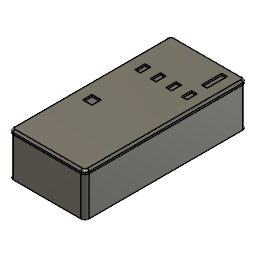
C_involucro_modulo_controle (Autodesk Fusion 360 design; units mm, degrees)
Autodesk Fusion 360 part; units mm, degrees
(part 1 of 2)
sketch "Esboço1" plane through (0, 0, 0) normal (0, 0, 1) x (1, 0, 0)
  line L0 (0, 0) -> (28, 0)
  line L1 (0, 0) -> (0, 10)
  line L2 (0, 10) -> (4, 10)
  line L3 (4, 10) -> (4, 8)
  line L4 (4, 8) -> (2, 8)
  line L5 (2, 8) -> (2, 6)
  line L6 (2, 6) -> (4, 6)
  line L7 (4, 6) -> (4, 4)
  line L8 (4, 4) -> (2, 4)
  line L9 (2, 4) -> (2, 2)
  line L10 (2, 2) -> (28, 2)
  line L11 (28, 2) -> (28, 0)
  line L12 (28, 2) -> (28, 0)
  line L13 (28, 2) -> (28, 0)
  line L14 (56, 0) -> (28, 0)
  line L15 (52, 4) -> (54, 4)
  line L16 (54, 2) -> (28, 2)
  line L17 (56, 10) -> (52, 10)
  line L18 (52, 10) -> (52, 8)
  line L19 (54, 4) -> (54, 2)
  line L20 (54, 6) -> (52, 6)
  line L21 (28, 2) -> (28, 0)
  line L22 (52, 6) -> (52, 4)
  line L23 (52, 8) -> (54, 8)
  line L24 (54, 8) -> (54, 6)
  line L25 (56, 0) -> (56, 10)
  point P0 (56, 0)
  dimension "d2" = 10
  dimension "d3" = 4
  dimension "d4" = 2
  dimension "d5" = 2
  dimension "d6" = 2
  dimension "d7" = 2
  dimension "d8" = 2
  dimension "d9" = 2
  dimension "d10" = 2
  dimension "d11" = 26
  constraint coincident L0.start L1.start
  constraint horizontal L0
  constraint perpendicular L0 L1
  constraint perpendicular L1 L2
  constraint perpendicular L2 L3
  constraint perpendicular L1 L4
  constraint perpendicular L4 L5
  constraint perpendicular L5 L6
  constraint perpendicular L6 L7
  constraint perpendicular L7 L8
  constraint perpendicular L0 L9
  constraint perpendicular L9 L10
  constraint symmetric L10.end L11 L12.start
  constraint symmetric L0.end L11 L12.end
  constraint perpendicular L10 L12
  constraint symmetric L0.start L12 L14.start
  constraint symmetric L0.start L12 P0
  constraint symmetric L1.end L12 L17.start
  constraint symmetric L2.end L12 L17.end
  constraint symmetric L3.end L12 L18.end
  constraint symmetric L4.end L12 L23.end
  constraint symmetric L5.end L12 L20.start
  constraint symmetric L6.end L12 L20.end
  constraint symmetric L7.end L12 L15.start
  constraint symmetric L8.end L12 L15.end
  constraint symmetric L9.end L12 L16.start
  constraint symmetric L10.end L12 L11.start
  constraint symmetric L0.end L12 L11.end
  measures "d2" distance of L0.start L1.end
  measures "d3" distance of L1.end L2.end
  measures "d4" distance of L2.end L3.end
  measures "d5" distance of L3.end L4.end
  measures "d6" distance of L4.end L5.end
  measures "d7" distance of L5.end L6.end
  measures "d8" distance of L6.end L7.end
  measures "d9" distance of L7.end L8.end
  measures "d10" distance of L8.end L9.end
  measures "d11" distance of L9.end L10.end
extrude "Extrusão1" add sketch "Esboço1" along normal blind 75 makes body 1
fillet "Arredondamento1" radius 2 1 edges at (0, 10, 37.5) on bodies 1
fillet "Arredondamento1" radius 2 1 edges at (56, 10, 37.5) on bodies 1
sketch "Esboço3" plane through (0, 0, 75) normal (0, 0, 1) x (1, 0, 0)
  line L0 (54, 2) -> (2, 2)
  line L1 (2, 2) -> (2, 4)
  line L2 (2, 4) -> (4, 4)
  line L3 (4, 4) -> (4, 6)
  line L4 (4, 6) -> (2, 6)
  line L5 (2, 6) -> (2, 8)
  line L6 (2, 8) -> (4, 8)
  line L7 (4, 8) -> (4, 10)
  line L8 (4, 10) -> (2, 10)
  arc A0 (2, 10) -> (0, 8) centre (2, 8) ccw
  line L9 (0, 8) -> (0, 0)
  line L10 (0, 0) -> (56, 0)
  line L11 (2, 8) -> (4, 8)
  line L12 (4, 8) -> (4, 6)
  line L13 (4, 6) -> (2, 6)
  line L14 (2, 6) -> (2, 8)
  line L15 (52, 8) -> (54, 8)
  line L16 (54, 8) -> (54, 6)
  line L17 (54, 6) -> (52, 6)
  line L18 (52, 6) -> (52, 8)
  line L19 (56, 0) -> (56, 8)
  line L20 (54, 10) -> (52, 10)
  line L21 (52, 10) -> (52, 8)
  line L22 (52, 8) -> (54, 8)
  line L23 (54, 8) -> (54, 6)
  line L24 (54, 6) -> (52, 6)
  line L25 (52, 6) -> (52, 4)
  line L26 (52, 4) -> (54, 4)
  line L27 (54, 4) -> (54, 2)
  arc A1 (56, 8) -> (54, 10) centre (54, 8) ccw
  constraint horizontal L11
  constraint vertical L12
  constraint horizontal L13
  constraint vertical L14
  constraint coincident L3.end L4.start
  constraint coincident L5.end L6.start
  constraint horizontal L15
  constraint vertical L16
  constraint horizontal L17
  constraint vertical L18
copy_body "Corpo -> Componente1" bodies 1 removing the originals makes body 2 in component "Placa 5x7"
extrude "Extrusão1'" add sketch "Esboço3" against normal blind 2 contours L15 L16 L17 L18 L22 L23 L24 | L4 L5 L6 L11 L12 L13 L14 bodies 2 in component "Placa 5x7"
sketch "Esboço7" plane through (0, 0, 0) normal (0, -1, 0) x (1, 0, 0)
  line L0 (0, 0) -> (56, 0)
  line L1 (56, 75) -> (0, 75)
  line L2 (0, 75) -> (0, 0)
  line L3 (0, 0) -> (0, 37.5)
  line L4 (0, 37.5) -> (28, 37.5)
  line L5 (67, -48.75) -> (-11, -48.75)
  line L6 (-11, -48.75) -> (-11, 123.75)
  line L7 (-11, 123.75) -> (67, 123.75)
  line L8 (67, 123.75) -> (67, -48.75)
  line L9 (67, -48.75) -> (-11, 123.75) construction
  line L10 (-11, -48.75) -> (67, 123.75) construction
  line L11 (65, 125.75) -> (-9, 125.75)
  line L12 (-13, 121.75) -> (-13, -46.75)
  line L13 (-9, -50.75) -> (65, -50.75)
  line L14 (69, -46.75) -> (69, 121.75)
  line L15 (69, 125.75) -> (-13, -50.75) construction
  line L16 (-13, 125.75) -> (69, -50.75) construction
  arc A0 (-9, 125.75) -> (-13, 121.75) centre (-9, 121.75) ccw
  arc A1 (69, 121.75) -> (65, 125.75) centre (65, 121.75) ccw
  arc A2 (65, -50.75) -> (69, -46.75) centre (65, -46.75) ccw
  arc A3 (-13, -46.75) -> (-9, -50.75) centre (-9, -46.75) ccw
  line L17 (56, 0) -> (56, 75)
  point P0 (28, 37.5)
  point P1 (28, 37.5)
  dimension "d45" = 37.5
  dimension "d46" = 28
  dimension "d47" = 172.5
  dimension "d48" = 78
  dimension "d49" = 82
  dimension "d50" = 176.5
  dimension "d54" = 4
  constraint coincident L0.start L2.end
  constraint perpendicular L0 L3
  constraint perpendicular L3 L4
  constraint horizontal L5
  constraint perpendicular L5 L6
  constraint parallel L5 L7
  constraint parallel L6 L8
  constraint coincident L9 P1
  constraint coincident L10 P1
  constraint coincident P1 P0
  constraint horizontal L11
  constraint perpendicular L11 L12
  constraint parallel L11 L13
  constraint parallel L12 L14
  constraint coincident L15 P1
  constraint coincident L16 P1
  constraint coincident L16.start L12
  constraint coincident L16.start L11
  constraint tangent L12 A0
  constraint tangent L11 A0
  constraint coincident L15.start L11
  constraint coincident L15.start L14
  constraint tangent L11 A1
  constraint tangent L14 A1
  constraint equal A0 A1
  constraint coincident L16.end L13
  constraint coincident L16.end L14
  constraint tangent L13 A2
  constraint tangent L14 A2
  constraint equal A0 A2
  constraint coincident L15.end L13
  constraint coincident L15.end L12
  constraint tangent L13 A3
  constraint tangent L12 A3
  constraint equal A0 A3
  measures "d45" distance of L0.start L3.end
  measures "d46" distance of L3.end P1
  measures "d47" distance of L5.end L6.end
  measures "d48" distance of L6.end L7.end
  measures "d49" distance of L15.end L16.end
  measures "d50" distance of L16.start L15.end
  measures "d54" radius of A0
extrude "Extrusão8" add sketch "Esboço7" against normal blind 41 thin wall 1 centred separate body contours L11 L12 L13 L14 A0 A1 A2 A3 makes body 3
copy_body "Corpo -> Componente2" bodies 3 removing the originals makes body 4 in component "Suporte Placa (1)"
extrude "Extrusão1''" add sketch "Esboço7" along normal blind 2 contours L0 L1 L2 L3 L17 | L5 L6 L7 L8 | L11 L12 L13 L14 A0 A1 A2 A3 bodies 4 in component "Suporte Placa (1)"
extrude "Extrusão11" add 1 faces at (41.6667, -2, 65.5833) along direction (0, 1, 0) blind 2 thin wall 0.5 outside on bodies 4 bodies 4 in component "Suporte Placa (1)"
sketch "Esboço1 (2)" plane through (0, 41, 0) normal (0, 1, 0) x (-1, 0, 0) in component "Suporte Placa (1)"
  arc A0 (12.5, 121.75) -> (11.5, 124.1995) centre (9, 121.75) ccw
  line L0 (12.5, 121.75) -> (12.5, -46.75)
  arc A1 (11.5, -49.1995) -> (12.5, -46.75) centre (9, -46.75) ccw
  line L1 (11.5, -49.1995) -> (11.5, 124.1995)
  arc A2 (-65, 125.25) -> (-67.4495, 124.25) centre (-65, 121.75) ccw
  line L2 (-65, 125.25) -> (9, 125.25)
  arc A3 (11.4495, 124.25) -> (9, 125.25) centre (9, 121.75) ccw
  line L3 (11.4495, 124.25) -> (-67.4495, 124.25)
  arc A4 (9, -50.25) -> (11.4495, -49.25) centre (9, -46.75) ccw
  line L4 (9, -50.25) -> (-65, -50.25)
  arc A5 (-67.4495, -49.25) -> (-65, -50.25) centre (-65, -46.75) ccw
  line L5 (-67.4495, -49.25) -> (11.4495, -49.25)
  arc A6 (-68.5, -46.75) -> (-67.5, -49.1995) centre (-65, -46.75) ccw
  line L6 (-68.5, -46.75) -> (-68.5, 121.75)
  arc A7 (-67.5, 124.1995) -> (-68.5, 121.75) centre (-65, 121.75) ccw
  line L7 (-67.5, 124.1995) -> (-67.5, -49.1995)
  line L8 (-66.5, 123.25) -> (10.5, 123.25)
  line L9 (10.5, 123.25) -> (10.5, -48.25)
  line L10 (10.5, -48.25) -> (-66.5, -48.25)
  line L11 (-66.5, -48.25) -> (-66.5, 123.25)
  arc A8 (9, -51.25) -> (13.5, -46.75) centre (9, -46.75) ccw
  line L12 (13.5, -46.75) -> (13.5, 121.75)
  arc A9 (13.5, 121.75) -> (9, 126.25) centre (9, 121.75) ccw
  line L13 (9, 126.25) -> (-65, 126.25)
  arc A10 (-65, 126.25) -> (-69.5, 121.75) centre (-65, 121.75) ccw
  line L14 (-69.5, 121.75) -> (-69.5, -46.75)
  line L15 (-65, -51.25) -> (9, -51.25)
  line L16 (10.5, -48.25) -> (10.5, -46.25)
  line L17 (10.5, -48.25) -> (8.5, -48.25)
  line L18 (8.5, -48.25) -> (8.5, -51.25)
  line L19 (10.5, -46.25) -> (13.5, -46.25)
  line L20 (-42.25, -3.25) -> (-42.75, -3.25)
  line L21 (-47.25, 1.25) -> (-47.25, 1.75)
  line L22 (-28, -51.25) -> (-28, -15.5)
  line L23 (-28, -15.5) -> (13.5, 37.5)
  arc A11 (-68.2911, 17.2939) -> (-71.5805, 11.846) centre (-67.2118, 12.9253) ccw
  line L24 (-68.5481, 12.0801) -> (-71.4606, 11.3606)
  line L25 (-69.0278, 14.0218) -> (-68.5481, 12.0801)
  line L26 (-67.0862, 14.5014) -> (-67.8057, 17.4139)
  line L27 (-67.0862, 14.5014) -> (10.5, 123.25)
  line L28 (-66.5, -46.25) -> (-69.5, -46.25)
  line L29 (-66.5, -48.25) -> (-66.5, -46.25)
  line L30 (-66.5, -48.25) -> (-64.5, -48.25)
  line L31 (-64.5, -48.25) -> (-64.5, -51.25)
  arc A12 (-69.5, -46.75) -> (-65, -51.25) centre (-65, -46.75) ccw
  line L32 (11.0862, 14.5014) -> (11.8057, 17.4139)
  line L33 (11.0862, 14.5014) -> (-66.5, 123.25)
  line L34 (13.0278, 14.0218) -> (12.5481, 12.0801)
  line L35 (12.5481, 12.0801) -> (15.4606, 11.3606)
  arc A13 (15.5805, 11.846) -> (12.2911, 17.2939) centre (11.2118, 12.9253) ccw
  dimension "d57" = 2
  dimension "d58" = 2
  dimension "d59" = 35.75
  constraint coincident L9.end L10.start
  constraint perpendicular L10 L16
  constraint perpendicular L16 L17
  constraint coincident L15 L18.end
  constraint perpendicular L15 L18
  constraint coincident L12 L19.end
  constraint perpendicular L12 L19
  constraint midpoint L15 L22.start
  constraint perpendicular L10 L22
  constraint midpoint L12 L23.end
  constraint symmetric A8.start L23 A11.end
  constraint symmetric A8.end L23 A11.start
  constraint symmetric A8 L23 A11
  constraint symmetric L16.end L23 L26.start
  constraint symmetric L9.end L23 L25.start
  constraint symmetric L17.end L23 L24.start
  constraint symmetric L18.end L23 L24.end
  constraint symmetric L19.end L23 L26.end
  constraint coincident L8.end L9.start
  constraint symmetric A8.start L22 L15.start
  constraint symmetric A8.end L22 L14.end
  constraint symmetric A8 L22 A12
  constraint symmetric L9.end L22 L10.end
  constraint symmetric L16.end L22 L28.start
  constraint symmetric L17.end L22 L30.end
  constraint symmetric L18.end L22 L31.end
  constraint symmetric L19.end L22 L28.end
  constraint symmetric L22 A11.end A13.start
  constraint symmetric L22 A11.start A13.end
  constraint symmetric L22 A11 A13
  constraint symmetric L22 L24.start L34.end
  constraint symmetric L22 L24.end L35.end
  constraint symmetric L22 L25.start L34.start
  constraint symmetric L22 L26.start L32.start
  constraint symmetric L22 L26.end L32.end
  constraint symmetric L22 L8.end L8.start
  measures "d57" distance of L9.end L16.end
  measures "d58" distance of L9.end L17.end
  measures "d59" distance of L22.start L22.end
ref_plane "Plano de trabalho1" through (28, 41, 37.5) normal (0, 1, 0) x (-1, 0, 0) in component "Suporte Placa (1)"
sketch "Esboço3 (2)" plane through (0, 41, 0) normal (0, 1, 0) x (1, 0, 0) in component "Suporte Placa (1)"
extrude "Extrusão7" add 1 faces at (67.1667, 41, 8.9167) along direction (0, 1, 0) blind 2 separate body on bodies 4 makes body 5 in component "Suporte Placa (1)"
copy_body "CutPasteBodies1" bodies 5 removing the originals makes body 6 in component "Tampa"
sketch "Esboço1 (3)" plane through (0, 43, 0) normal (0, 1, 0) x (-1, 0, 0) in component "Tampa"
  line L0 (-66.5, -48.25) -> (-66.5, 123.25)
  line L1 (-66.5, 123.25) -> (10.5, 123.25)
  line L2 (10.5, 123.25) -> (10.5, -48.25)
  line L3 (10.5, -48.25) -> (-66.5, -48.25)
  line L4 (-67.5, 124.1995) -> (-67.5, -49.1995)
  line L5 (-68.5, -46.75) -> (-68.5, 121.75)
  line L6 (-69.5, 121.75) -> (-69.5, -46.75)
  arc A0 (-69.5, -46.75) -> (-65, -51.25) centre (-65, -46.75) ccw
  line L7 (-65, -51.25) -> (9, -51.25)
  arc A1 (9, -51.25) -> (13.5, -46.75) centre (9, -46.75) ccw
  line L8 (13.5, -46.75) -> (13.5, 121.75)
  arc A2 (13.5, 121.75) -> (9, 126.25) centre (9, 121.75) ccw
  line L9 (9, 126.25) -> (-65, 126.25)
  arc A3 (-65, 126.25) -> (-69.5, 121.75) centre (-65, 121.75) ccw
  line L10 (12.5, 121.75) -> (12.5, -46.75)
  line L11 (11.5, -49.1995) -> (11.5, 124.1995)
  line L12 (-65, 125.25) -> (9, 125.25)
  line L13 (11.4495, 124.25) -> (-67.4495, 124.25)
  line L14 (9, -50.25) -> (-65, -50.25)
  line L15 (-67.4495, -49.25) -> (11.4495, -49.25)
  arc A4 (12.5, 121.75) -> (11.5, 124.1995) centre (9, 121.75) ccw
  arc A5 (11.5, -49.1995) -> (12.5, -46.75) centre (9, -46.75) ccw
  arc A6 (-65, 125.25) -> (-67.4495, 124.25) centre (-65, 121.75) ccw
  arc A7 (11.4495, 124.25) -> (9, 125.25) centre (9, 121.75) ccw
  arc A8 (9, -50.25) -> (11.4495, -49.25) centre (9, -46.75) ccw
  arc A9 (-67.4495, -49.25) -> (-65, -50.25) centre (-65, -46.75) ccw
  arc A10 (-68.5, -46.75) -> (-67.5, -49.1995) centre (-65, -46.75) ccw
  arc A11 (-67.5, 124.1995) -> (-68.5, 121.75) centre (-65, 121.75) ccw
extrude "Extrusão1'''" add sketch "Esboço1 (3)" along normal blind 2 contours L0 L1 L2 L3 | L4 L5 A10 A11 | L6 A0 L7 A1 L8 A2 L9 A3 | L10 L11 A4 A5 | L12 L13 A6 A7 | L14 L15 A8 A9 bodies 6 in component "Tampa"
extrude "Extrusão6" add sketch "Esboço1 (3)" along normal blind 2 and the other way blind 4 contours L4 L5 A10 A11 | L10 L11 A4 A5 | L12 L13 A6 A7 | L14 L15 A8 A9 bodies 6 in component "Tampa"
fillet "Arredondamento1'" radius 2 8 edges at (69.5, 45, 37.5) (68.182, 45, -49.932) (28, 45, -51.25) (-12.182, 45, -49.932) (-13.5, 45, 37.5) (-12.182, 45, 124.932) (28, 45, 126.25) (68.182, 45, 124.932) on bodies 6 in component "Tampa"
sketch "Esboço11" plane through (0, 45, 0) normal (0, 1, 0) x (-1, 0, 0)
  line L0 (-67.5, 121.75) -> (-67.5, -46.75)
  arc A0 (-67.5, -46.75) -> (-65, -49.25) centre (-65, -46.75) ccw
  line L1 (-65, -49.25) -> (9, -49.25)
  arc A1 (9, -49.25) -> (11.5, -46.75) centre (9, -46.75) ccw
  line L2 (11.5, -46.75) -> (11.5, 121.75)
  arc A2 (11.5, 121.75) -> (9, 124.25) centre (9, 121.75) ccw
  line L3 (9, 124.25) -> (-65, 124.25)
  arc A3 (-65, 124.25) -> (-67.5, 121.75) centre (-65, 121.75) ccw
  spline S0 degree 3 poles (-31.7483, 30.1834) (-31.8055, 30.363) (-32.0097, 30.8122) (-32.1975, 31.1797) knots 0 0 0 0 1 1 1 1
  line L4 (-32.1975, 31.1797) -> (-32.5487, 31.8576)
  line L5 (-32.5487, 31.8576) -> (-33.3408, 32.0944)
  spline S1 degree 3 poles (-33.3408, 32.0944) (-35.6847, 32.8131) (-37.2037, 33.2541) (-37.2364, 33.2296) knots 0 0 0 0 1 1 1 1
  spline S2 degree 3 poles (-37.2364, 33.2296) (-37.2528, 33.2133) (-37.1221, 32.9192) (-36.9424, 32.5762) knots 0 0 0 0 1 1 1 1
  spline S3 degree 3 poles (-36.9424, 32.5762) (-36.1992, 31.1552) (-36.2319, 30.1752) (-37.0567, 29.2605) knots 0 0 0 0 1 1 1 1
  line L6 (-37.0567, 29.2605) -> (-37.3589, 28.9257)
  line L7 (-37.3589, 28.9257) -> (-37.0894, 28.8522)
  spline S4 degree 3 poles (-37.0894, 28.8522) (-36.9424, 28.8113) (-35.8726, 28.4928) (-34.7129, 28.1417) knots 0 0 0 0 1 1 1 1
  line L8 (-34.7129, 28.1417) -> (-32.6058, 27.5128)
  line L9 (-32.6058, 27.5128) -> (-32.3608, 27.7415)
  spline S5 degree 3 poles (-32.3608, 27.7415) (-32.2302, 27.8722) (-32.0097, 28.1907) (-31.879, 28.4602) knots 0 0 0 0 1 1 1 1
  spline S6 degree 3 poles (-31.879, 28.4602) (-31.6095, 28.9992) (-31.5605, 29.5954) (-31.7483, 30.1834) knots 0 0 0 0 1 1 1 1
  spline S7 degree 3 poles (-32.663, 27.2433) (-32.6793, 27.1943) (-32.908, 26.3613) (-33.1775, 25.3813) knots 0 0 0 0 1 1 1 1
  spline S8 degree 3 poles (-33.1775, 25.3813) (-33.4389, 24.4013) (-33.6757, 23.5764) (-33.7002, 23.5519) knots 0 0 0 0 1 1 1 1
  spline S9 degree 3 poles (-33.7002, 23.5519) (-33.7247, 23.5274) (-34.5495, 23.7479) (-35.5296, 24.0338) knots 0 0 0 0 1 1 1 1
  line L10 (-35.5296, 24.0338) -> (-37.3099, 24.5564)
  line L11 (-37.3099, 24.5564) -> (-37.3344, 26.7125)
  line L12 (-37.3344, 26.7125) -> (-37.3589, 28.8767)
  line L13 (-37.3589, 28.8767) -> (-37.8816, 26.9575)
  spline S10 degree 3 poles (-37.8816, 26.9575) (-38.3798, 25.1444) (-38.4043, 24.9893) (-38.4124, 24.1318) knots 0 0 0 0 1 1 1 1
  line L14 (-38.4124, 24.1318) -> (-38.4124, 23.2252)
  line L15 (-38.4124, 23.2252) -> (-37.5304, 22.9802)
  line L16 (-37.5304, 22.9802) -> (-36.6566, 22.7352)
  line L17 (-36.6566, 22.7352) -> (-36.6321, 22.1636)
  line L18 (-36.6321, 22.1636) -> (-36.6076, 21.5919)
  line L19 (-36.6076, 21.5919) -> (-36.1257, 21.4612)
  spline S11 degree 3 poles (-36.1257, 21.4612) (-35.8562, 21.3795) (-35.6031, 21.3224) (-35.5541, 21.3224) knots 0 0 0 0 1 1 1 1
  spline S12 degree 3 poles (-35.5541, 21.3224) (-35.5051, 21.3224) (-35.4724, 21.5511) (-35.4724, 21.8614) knots 0 0 0 0 1 1 1 1
  spline S13 degree 3 poles (-35.4724, 21.8614) (-35.4724, 22.3187) (-35.4561, 22.3922) (-35.3417, 22.3514) knots 0 0 0 0 1 1 1 1
  spline S14 degree 3 poles (-35.3417, 22.3514) (-35.2682, 22.3269) (-35.1212, 22.2779) (-35.015, 22.2534) knots 0 0 0 0 1 1 1 1
  spline S15 degree 3 poles (-35.015, 22.2534) (-34.8272, 22.2044) (-34.819, 22.1717) (-34.819, 21.5592) knots 0 0 0 0 1 1 1 1
  line L20 (-34.819, 21.5592) -> (-34.819, 20.9222)
  line L21 (-34.819, 20.9222) -> (-34.3454, 20.7834)
  spline S16 degree 3 poles (-34.3454, 20.7834) (-34.0922, 20.7099) (-33.8309, 20.6282) (-33.7737, 20.6119) knots 0 0 0 0 1 1 1 1
  spline S17 degree 3 poles (-33.7737, 20.6119) (-33.7002, 20.5792) (-33.6757, 20.8895) (-33.6757, 22.0084) knots 0 0 0 0 1 1 1 1
  line L22 (-33.6757, 22.0084) -> (-33.6757, 23.4458)
  line L23 (-33.6757, 23.4458) -> (-33.447, 23.3967)
  spline S18 degree 3 poles (-33.447, 23.3967) (-33.3245, 23.3641) (-33.1448, 23.3069) (-33.0387, 23.2742) knots 0 0 0 0 1 1 1 1
  spline S19 degree 3 poles (-33.0387, 23.2742) (-32.5977, 23.1109) (-32.614, 23.0374) (-32.6222, 25.2588) knots 0 0 0 0 1 1 1 1
  spline S20 degree 3 poles (-32.6222, 25.2588) (-32.6222, 26.394) (-32.6385, 27.2842) (-32.663, 27.2433) knots 0 0 0 0 1 1 1 1
  spline S21 degree 3 poles (-33.6757, 7.9778) (-33.8227, 8.4597) (-34.2719, 9.0232) (-34.6557, 9.211) knots 0 0 0 0 1 1 1 1
  spline S22 degree 3 poles (-34.6557, 9.211) (-35.3009, 9.5377) (-35.6684, 9.4315) (-36.5096, 8.6557) knots 0 0 0 0 1 1 1 1
  spline S23 degree 3 poles (-36.5096, 8.6557) (-36.7056, 8.476) (-36.8852, 8.3372) (-36.9261, 8.3372) knots 0 0 0 0 1 1 1 1
  spline S24 degree 3 poles (-36.9261, 8.3372) (-36.9669, 8.3372) (-37.0649, 8.4107) (-37.1466, 8.5005) knots 0 0 0 0 1 1 1 1
  spline S25 degree 3 poles (-37.1466, 8.5005) (-37.3589, 8.7373) (-37.3263, 9.162) (-37.0812, 9.5867) knots 0 0 0 0 1 1 1 1
  line L24 (-37.0812, 9.5867) -> (-36.8689, 9.9379)
  line L25 (-36.8689, 9.9379) -> (-37.4733, 10.1175)
  spline S26 degree 3 poles (-37.4733, 10.1175) (-37.8081, 10.2155) (-38.1184, 10.2972) (-38.1593, 10.2972) knots 0 0 0 0 1 1 1 1
  spline S27 degree 3 poles (-38.1593, 10.2972) (-38.2001, 10.2972) (-38.2981, 10.1339) (-38.3716, 9.9297) knots 0 0 0 0 1 1 1 1
  spline S28 degree 3 poles (-38.3716, 9.9297) (-38.5758, 9.407) (-38.5104, 8.2718) (-38.2573, 7.7655) knots 0 0 0 0 1 1 1 1
  spline S29 degree 3 poles (-38.2573, 7.7655) (-38.0204, 7.3) (-37.7183, 6.9733) (-37.3508, 6.7936) knots 0 0 0 0 1 1 1 1
  spline S30 degree 3 poles (-37.3508, 6.7936) (-36.6157, 6.418) (-36.2564, 6.5078) (-35.6031, 7.1938) knots 0 0 0 0 1 1 1 1
  spline S31 degree 3 poles (-35.6031, 7.1938) (-35.3499, 7.4633) (-35.0967, 7.6838) (-35.0395, 7.6838) knots 0 0 0 0 1 1 1 1
  spline S32 degree 3 poles (-35.0395, 7.6838) (-34.7129, 7.6838) (-34.623, 7.006) (-34.9007, 6.5568) knots 0 0 0 0 1 1 1 1
  spline S33 degree 3 poles (-34.9007, 6.5568) (-35.0885, 6.2546) (-35.1212, 6.2873) (-34.3372, 6.0505) knots 0 0 0 0 1 1 1 1
  line L26 (-34.3372, 6.0505) -> (-33.8309, 5.9034)
  line L27 (-33.8309, 5.9034) -> (-33.741, 6.1158)
  spline S34 degree 3 poles (-33.741, 6.1158) (-33.6185, 6.4098) (-33.5777, 7.6593) (-33.6757, 7.9778) knots 0 0 0 0 1 1 1 1
  spline S35 degree 3 poles (-35.9787, 20.8732) (-37.2528, 21.5837) (-38.3144, 22.1799) (-38.3471, 22.1962) knots 0 0 0 0 1 1 1 1
  spline S36 degree 3 poles (-38.3471, 22.1962) (-38.3879, 22.2126) (-38.4124, 21.8777) (-38.4124, 21.453) knots 0 0 0 0 1 1 1 1
  line L28 (-38.4124, 21.453) -> (-38.4124, 20.669)
  line L29 (-38.4124, 20.669) -> (-38.0858, 20.5057)
  line L30 (-38.0858, 20.5057) -> (-37.7591, 20.3424)
  line L31 (-37.7591, 20.3424) -> (-37.7591, 19.8442)
  line L32 (-37.7591, 19.8442) -> (-37.7591, 19.346)
  line L33 (-37.7591, 19.346) -> (-38.0858, 19.4032)
  line L34 (-38.0858, 19.4032) -> (-38.4124, 19.4603)
  line L35 (-38.4124, 19.4603) -> (-38.4124, 18.6355)
  line L36 (-38.4124, 18.6355) -> (-38.4124, 17.8107)
  line L37 (-38.4124, 17.8107) -> (-37.2037, 17.8107)
  spline S37 degree 3 poles (-37.2037, 17.8107) (-36.5422, 17.8107) (-35.4806, 17.7862) (-34.8354, 17.7535) knots 0 0 0 0 1 1 1 1
  line L38 (-34.8354, 17.7535) -> (-33.6757, 17.7045)
  line L39 (-33.6757, 17.7045) -> (-33.6757, 18.6437)
  line L40 (-33.6757, 18.6437) -> (-33.6757, 19.5829)
  line L41 (-33.6757, 19.5829) -> (-35.9787, 20.8732)
  line L42 (-35.9787, 19.1418) -> (-36.7791, 19.2235)
  line L43 (-36.7791, 19.2235) -> (-36.7791, 19.542)
  spline S38 degree 3 poles (-36.7791, 19.542) (-36.7791, 19.7135) (-36.7627, 19.8524) (-36.7464, 19.8524) knots 0 0 0 0 1 1 1 1
  spline S39 degree 3 poles (-36.7464, 19.8524) (-36.6729, 19.8524) (-35.1294, 19.1092) (-35.1539, 19.0847) knots 0 0 0 0 1 1 1 1
  spline S40 degree 3 poles (-35.1539, 19.0847) (-35.1702, 19.0765) (-35.5459, 19.101) (-35.9787, 19.1418) knots 0 0 0 0 1 1 1 1
  spline S41 degree 3 poles (-33.937, 16.4141) (-34.084, 16.455) (-35.1049, 16.7571) (-36.1992, 17.0756) knots 0 0 0 0 1 1 1 1
  spline S42 degree 3 poles (-36.1992, 17.0756) (-37.2936, 17.4023) (-38.2409, 17.68) (-38.3063, 17.7045) knots 0 0 0 0 1 1 1 1
  spline S43 degree 3 poles (-38.3063, 17.7045) (-38.3961, 17.7372) (-38.4124, 17.5983) (-38.3961, 16.9123) knots 0 0 0 0 1 1 1 1
  line L44 (-38.3961, 16.9123) -> (-38.3716, 16.0711)
  line L45 (-38.3716, 16.0711) -> (-37.6366, 15.8588)
  line L46 (-37.6366, 15.8588) -> (-36.9016, 15.6465)
  line L47 (-36.9016, 15.6465) -> (-36.8444, 15.1238)
  spline S44 degree 3 poles (-36.8444, 15.1238) (-36.7546, 14.2989) (-36.5586, 13.8253) (-36.1339, 13.4006) knots 0 0 0 0 1 1 1 1
  spline S45 degree 3 poles (-36.1339, 13.4006) (-35.7256, 12.9922) (-35.3172, 12.8289) (-34.721, 12.8289) knots 0 0 0 0 1 1 1 1
  spline S46 degree 3 poles (-34.721, 12.8289) (-33.9125, 12.8289) (-33.6757, 13.3597) (-33.6757, 15.1646) knots 0 0 0 0 1 1 1 1
  line L48 (-33.6757, 15.1646) -> (-33.6757, 16.3243)
  line L49 (-33.6757, 16.3243) -> (-33.937, 16.4141)
  spline S47 degree 3 poles (-34.7864, 14.5603) (-34.8517, 14.4623) (-34.9824, 14.3806) (-35.0722, 14.3806) knots 0 0 0 0 1 1 1 1
  spline S48 degree 3 poles (-35.0722, 14.3806) (-35.3091, 14.3806) (-35.7174, 14.8134) (-35.7174, 15.0666) knots 0 0 0 0 1 1 1 1
  spline S49 degree 3 poles (-35.7174, 15.0666) (-35.7174, 15.1809) (-35.7092, 15.2789) (-35.6929, 15.2789) knots 0 0 0 0 1 1 1 1
  spline S50 degree 3 poles (-35.6929, 15.2789) (-35.6357, 15.2789) (-34.7782, 15.0176) (-34.7129, 14.9768) knots 0 0 0 0 1 1 1 1
  spline S51 degree 3 poles (-34.7129, 14.9768) (-34.623, 14.9196) (-34.6475, 14.7563) (-34.7864, 14.5603) knots 0 0 0 0 1 1 1 1
  spline S52 degree 3 poles (-35.9787, 12.8207) (-37.2528, 13.1882) (-38.3144, 13.4904) (-38.3471, 13.4822) knots 0 0 0 0 1 1 1 1
  spline S53 degree 3 poles (-38.3471, 13.4822) (-38.3879, 13.4822) (-38.4124, 12.8371) (-38.4124, 12.0531) knots 0 0 0 0 1 1 1 1
  line L50 (-38.4124, 12.0531) -> (-38.4124, 10.632)
  line L51 (-38.4124, 10.632) -> (-37.8734, 10.4605)
  spline S54 degree 3 poles (-37.8734, 10.4605) (-37.5794, 10.3707) (-37.3018, 10.2972) (-37.2609, 10.2972) knots 0 0 0 0 1 1 1 1
  spline S55 degree 3 poles (-37.2609, 10.2972) (-37.2201, 10.2972) (-37.1874, 10.5749) (-37.1874, 10.9179) knots 0 0 0 0 1 1 1 1
  spline S56 degree 3 poles (-37.1874, 10.9179) (-37.1874, 11.4569) (-37.1711, 11.5304) (-37.0567, 11.4895) knots 0 0 0 0 1 1 1 1
  spline S57 degree 3 poles (-37.0567, 11.4895) (-36.9832, 11.465) (-36.8362, 11.416) (-36.7301, 11.3915) knots 0 0 0 0 1 1 1 1
  spline S58 degree 3 poles (-36.7301, 11.3915) (-36.5586, 11.3507) (-36.5422, 11.2935) (-36.5177, 10.7627) knots 0 0 0 0 1 1 1 1
  line L52 (-36.5177, 10.7627) -> (-36.4932, 10.1829)
  line L53 (-36.4932, 10.1829) -> (-36.0032, 10.0359)
  spline S59 degree 3 poles (-36.0032, 10.0359) (-35.7337, 9.9542) (-35.4887, 9.8889) (-35.4479, 9.8889) knots 0 0 0 0 1 1 1 1
  spline S60 degree 3 poles (-35.4479, 9.8889) (-35.4152, 9.8889) (-35.3907, 10.1257) (-35.3907, 10.4197) knots 0 0 0 0 1 1 1 1
  spline S61 degree 3 poles (-35.3907, 10.4197) (-35.3907, 10.975) (-35.3744, 10.9995) (-34.9987, 10.9015) knots 0 0 0 0 1 1 1 1
  spline S62 degree 3 poles (-34.9987, 10.9015) (-34.8354, 10.8525) (-34.819, 10.8035) (-34.819, 10.2074) knots 0 0 0 0 1 1 1 1
  line L54 (-34.819, 10.2074) -> (-34.819, 9.5703)
  line L55 (-34.819, 9.5703) -> (-34.3454, 9.4315)
  spline S63 degree 3 poles (-34.3454, 9.4315) (-34.0922, 9.358) (-33.8309, 9.2763) (-33.7737, 9.26) knots 0 0 0 0 1 1 1 1
  spline S64 degree 3 poles (-33.7737, 9.26) (-33.7002, 9.2273) (-33.6757, 9.5458) (-33.6757, 10.681) knots 0 0 0 0 1 1 1 1
  line L56 (-33.6757, 10.681) -> (-33.6757, 12.1429)
  line L57 (-33.6757, 12.1429) -> (-35.9787, 12.8207)
  spline S65 degree 3 poles (-35.9542, 6.0341) (-37.2037, 6.4016) (-38.2736, 6.7038) (-38.3226, 6.7038) knots 0 0 0 0 1 1 1 1
  spline S66 degree 3 poles (-38.3226, 6.7038) (-38.3798, 6.7038) (-38.4124, 6.4343) (-38.4124, 5.8871) knots 0 0 0 0 1 1 1 1
  spline S67 degree 3 poles (-38.4124, 5.8871) (-38.4124, 5.3073) (-38.3879, 5.0704) (-38.3144, 5.0704) knots 0 0 0 0 1 1 1 1
  spline S68 degree 3 poles (-38.3144, 5.0704) (-38.2573, 5.0704) (-37.9143, 4.9806) (-37.5468, 4.8663) knots 0 0 0 0 1 1 1 1
  line L58 (-37.5468, 4.8663) -> (-36.8852, 4.6621)
  line L59 (-36.8852, 4.6621) -> (-36.8362, 4.0904)
  spline S69 degree 3 poles (-36.8362, 4.0904) (-36.7219, 2.7266) (-35.9379, 1.8935) (-34.7619, 1.8854) knots 0 0 0 0 1 1 1 1
  spline S70 degree 3 poles (-34.7619, 1.8854) (-34.3045, 1.8854) (-34.2474, 1.9099) (-34.0514, 2.1304) knots 0 0 0 0 1 1 1 1
  spline S71 degree 3 poles (-34.0514, 2.1304) (-33.741, 2.4979) (-33.6757, 2.8654) (-33.6757, 4.1803) knots 0 0 0 0 1 1 1 1
  line L60 (-33.6757, 4.1803) -> (-33.6757, 5.3726)
  line L61 (-33.6757, 5.3726) -> (-35.9542, 6.0341)
  spline S72 degree 3 poles (-34.7374, 3.6494) (-34.819, 3.4371) (-35.0477, 3.3717) (-35.3499, 3.4861) knots 0 0 0 0 1 1 1 1
  spline S73 degree 3 poles (-35.3499, 3.4861) (-35.5051, 3.5514) (-35.7174, 3.9352) (-35.7174, 4.1639) knots 0 0 0 0 1 1 1 1
  spline S74 degree 3 poles (-35.7174, 4.1639) (-35.7174, 4.3191) (-35.7011, 4.3191) (-35.2845, 4.2048) knots 0 0 0 0 1 1 1 1
  spline S75 degree 3 poles (-35.2845, 4.2048) (-34.672, 4.0251) (-34.6557, 4.0251) (-34.6557, 3.9352) knots 0 0 0 0 1 1 1 1
  spline S76 degree 3 poles (-34.6557, 3.9352) (-34.6557, 3.8944) (-34.6884, 3.7637) (-34.7374, 3.6494) knots 0 0 0 0 1 1 1 1
  spline S77 degree 3 poles (-20.6688, 26.652) (-20.7101, 26.8858) (-20.8545, 27.3052) (-21.0126, 27.6215) knots 0 0 0 0 1 1 1 1
  spline S78 degree 3 poles (-21.0126, 27.6215) (-21.5352, 28.6873) (-22.3878, 29.3061) (-23.6943, 29.5743) knots 0 0 0 0 1 1 1 1
  spline S79 degree 3 poles (-23.6943, 29.5743) (-24.1619, 29.6706) (-24.7257, 29.87) (-25.6058, 30.255) knots 0 0 0 0 1 1 1 1
  line L62 (-25.6058, 30.255) -> (-26.8573, 30.7983)
  line L63 (-26.8573, 30.7983) -> (-26.8573, 30.255)
  line L64 (-26.8573, 30.255) -> (-26.8573, 29.7118)
  line L65 (-26.8573, 29.7118) -> (-27.9575, 29.7118)
  line L66 (-27.9575, 29.7118) -> (-29.0576, 29.7118)
  line L67 (-29.0576, 29.7118) -> (-29.0714, 27.2364)
  spline S80 degree 2 poles (-29.0714, 27.2364) (-29.0851, 25.875) (-29.092, 24.7611) knots 0 0 0 1 1 1
  spline S81 degree 3 poles (-29.092, 24.7611) (-29.092, 24.7679) (-28.8926, 24.8229) (-28.6451, 24.8917) knots 0 0 0 0 1 1 1 1
  line L68 (-28.6451, 24.8917) -> (-28.1981, 25.0155)
  line L69 (-28.1981, 25.0155) -> (-28.1775, 26.9201)
  line L70 (-28.1775, 26.9201) -> (-28.1637, 28.8179)
  line L71 (-28.1637, 28.8179) -> (-27.098, 28.8179)
  line L72 (-27.098, 28.8179) -> (-26.0322, 28.8179)
  line L73 (-26.0322, 28.8179) -> (-26.0322, 29.1342)
  spline S82 degree 3 poles (-26.0322, 29.1342) (-26.0322, 29.3612) (-26.0047, 29.4437) (-25.9428, 29.4162) knots 0 0 0 0 1 1 1 1
  spline S83 degree 3 poles (-25.9428, 29.4162) (-24.5332, 28.8317) (-24.1275, 28.6804) (-23.7287, 28.6117) knots 0 0 0 0 1 1 1 1
  spline S84 degree 3 poles (-23.7287, 28.6117) (-21.9615, 28.316) (-21.047, 26.5626) (-21.8034, 24.9123) knots 0 0 0 0 1 1 1 1
  spline S85 degree 3 poles (-21.8034, 24.9123) (-22.4635, 23.4615) (-24.2994, 22.9458) (-25.6196, 23.8328) knots 0 0 0 0 1 1 1 1
  spline S86 degree 3 poles (-25.6196, 23.8328) (-25.819, 23.9634) (-25.9978, 24.0735) (-26.0253, 24.0735) knots 0 0 0 0 1 1 1 1
  spline S87 degree 3 poles (-26.0253, 24.0735) (-26.0459, 24.0735) (-26.7404, 23.8809) (-27.5587, 23.6471) knots 0 0 0 0 1 1 1 1
  line L74 (-27.5587, 23.6471) -> (-29.0576, 23.2208)
  line L75 (-29.0576, 23.2208) -> (-29.0576, 22.7876)
  spline S88 degree 3 poles (-29.0576, 22.7876) (-29.0576, 22.547) (-29.037, 22.3544) (-29.0026, 22.3544) knots 0 0 0 0 1 1 1 1
  spline S89 degree 3 poles (-29.0026, 22.3544) (-28.9751, 22.3544) (-28.3356, 22.5195) (-27.5862, 22.7189) knots 0 0 0 0 1 1 1 1
  line L76 (-27.5862, 22.7189) -> (-26.2178, 23.0902)
  line L77 (-26.2178, 23.0902) -> (-25.8671, 22.8976)
  spline S90 degree 3 poles (-25.8671, 22.8976) (-24.8564, 22.3476) (-23.4949, 22.3613) (-22.436, 22.9183) knots 0 0 0 0 1 1 1 1
  spline S91 degree 3 poles (-22.436, 22.9183) (-21.989, 23.1589) (-21.2946, 23.8603) (-21.0745, 24.2935) knots 0 0 0 0 1 1 1 1
  spline S92 degree 3 poles (-21.0745, 24.2935) (-20.6826, 25.0567) (-20.5519, 25.8544) (-20.6688, 26.652) knots 0 0 0 0 1 1 1 1
  spline S93 degree 3 poles (-21.9271, 26.7207) (-22.0853, 27.1814) (-22.2228, 27.3946) (-22.5873, 27.7384) knots 0 0 0 0 1 1 1 1
  spline S94 degree 3 poles (-22.5873, 27.7384) (-22.9861, 28.1166) (-23.213, 28.2266) (-23.7974, 28.3297) knots 0 0 0 0 1 1 1 1
  spline S95 degree 3 poles (-23.7974, 28.3297) (-24.0244, 28.371) (-24.5332, 28.5291) (-24.932, 28.6804) knots 0 0 0 0 1 1 1 1
  spline S96 degree 3 poles (-24.932, 28.6804) (-25.3308, 28.8317) (-25.6746, 28.9555) (-25.7021, 28.9555) knots 0 0 0 0 1 1 1 1
  spline S97 degree 3 poles (-25.7021, 28.9555) (-25.7227, 28.9555) (-25.764, 28.8592) (-25.7915, 28.7492) knots 0 0 0 0 1 1 1 1
  line L78 (-25.7915, 28.7492) -> (-25.8396, 28.5429)
  line L79 (-25.8396, 28.5429) -> (-26.8642, 28.5429)
  line L80 (-26.8642, 28.5429) -> (-27.8887, 28.5429)
  line L81 (-27.8887, 28.5429) -> (-27.8887, 26.817)
  spline S98 degree 3 poles (-27.8887, 26.817) (-27.8887, 25.1667) (-27.8818, 25.098) (-27.7581, 25.1392) knots 0 0 0 0 1 1 1 1
  spline S99 degree 3 poles (-27.7581, 25.1392) (-27.6893, 25.1599) (-27.4968, 25.2149) (-27.3317, 25.263) knots 0 0 0 0 1 1 1 1
  line L82 (-27.3317, 25.263) -> (-27.0292, 25.3524)
  line L83 (-27.0292, 25.3524) -> (-27.0086, 26.5007)
  line L84 (-27.0086, 26.5007) -> (-26.9948, 27.649)
  line L85 (-26.9948, 27.649) -> (-26.0734, 27.649)
  spline S100 degree 3 poles (-26.0734, 27.649) (-25.4202, 27.649) (-25.1383, 27.6765) (-25.1245, 27.7315) knots 0 0 0 0 1 1 1 1
  spline S101 degree 3 poles (-25.1245, 27.7315) (-25.1039, 27.7865) (-24.9457, 27.759) (-24.5951, 27.6284) knots 0 0 0 0 1 1 1 1
  spline S102 degree 3 poles (-24.5951, 27.6284) (-24.32, 27.5252) (-24.0381, 27.4427) (-23.9625, 27.4427) knots 0 0 0 0 1 1 1 1
  spline S103 degree 3 poles (-23.9625, 27.4427) (-23.7631, 27.4427) (-23.3436, 27.2089) (-23.1305, 26.982) knots 0 0 0 0 1 1 1 1
  spline S104 degree 3 poles (-23.1305, 26.982) (-22.3053, 26.1156) (-22.8417, 24.7267) (-24.0312, 24.6373) knots 0 0 0 0 1 1 1 1
  spline S105 degree 3 poles (-24.0312, 24.6373) (-24.6432, 24.596) (-25.0351, 24.7679) (-25.3721, 25.2493) knots 0 0 0 0 1 1 1 1
  line L86 (-25.3721, 25.2493) -> (-25.4752, 25.4074)
  line L87 (-25.4752, 25.4074) -> (-27.3042, 24.8917)
  line L88 (-27.3042, 24.8917) -> (-29.1264, 24.3829)
  line L89 (-29.1264, 24.3829) -> (-29.1264, 23.9222)
  line L90 (-29.1264, 23.9222) -> (-29.1264, 23.4684)
  line L91 (-29.1264, 23.4684) -> (-28.7963, 23.5646)
  spline S106 degree 3 poles (-28.7963, 23.5646) (-28.6176, 23.6196) (-27.8887, 23.8328) (-27.1805, 24.0459) knots 0 0 0 0 1 1 1 1
  line L92 (-27.1805, 24.0459) -> (-25.8878, 24.4241)
  line L93 (-25.8878, 24.4241) -> (-25.6058, 24.1835)
  spline S107 degree 3 poles (-25.6058, 24.1835) (-25.2208, 23.8534) (-24.7395, 23.6953) (-24.1069, 23.7021) knots 0 0 0 0 1 1 1 1
  spline S108 degree 3 poles (-24.1069, 23.7021) (-23.4743, 23.7021) (-23.0823, 23.8603) (-22.5941, 24.321) knots 0 0 0 0 1 1 1 1
  spline S109 degree 3 poles (-22.5941, 24.321) (-22.1128, 24.7679) (-21.8859, 25.2561) (-21.8584, 25.9231) knots 0 0 0 0 1 1 1 1
  spline S110 degree 3 poles (-21.8584, 25.9231) (-21.8446, 26.2325) (-21.879, 26.5557) (-21.9271, 26.7207) knots 0 0 0 0 1 1 1 1
  spline S111 degree 3 poles (-22.9104, 19.604) (-23.0548, 20.1541) (-23.3299, 20.5598) (-23.8112, 20.9242) knots 0 0 0 0 1 1 1 1
  spline S112 degree 3 poles (-23.8112, 20.9242) (-24.3957, 21.3643) (-24.8907, 21.5362) (-25.6952, 21.5774) knots 0 0 0 0 1 1 1 1
  spline S113 degree 3 poles (-25.6952, 21.5774) (-27.0842, 21.66) (-27.6205, 21.2061) (-27.7306, 19.8928) knots 0 0 0 0 1 1 1 1
  spline S114 degree 3 poles (-27.7306, 19.8928) (-27.8199, 18.7445) (-27.2492, 17.5756) (-26.431, 17.2386) knots 0 0 0 0 1 1 1 1
  spline S115 degree 3 poles (-26.431, 17.2386) (-26.2866, 17.1768) (-26.1559, 17.1286) (-26.1353, 17.1286) knots 0 0 0 0 1 1 1 1
  spline S116 degree 3 poles (-26.1353, 17.1286) (-26.1147, 17.1286) (-26.1009, 17.438) (-26.1009, 17.8162) knots 0 0 0 0 1 1 1 1
  line L94 (-26.1009, 17.8162) -> (-26.1009, 18.497)
  line L95 (-26.1009, 18.497) -> (-26.3003, 18.607)
  spline S117 degree 3 poles (-26.3003, 18.607) (-26.5891, 18.7514) (-26.7885, 19.1158) (-26.7885, 19.494) knots 0 0 0 0 1 1 1 1
  spline S118 degree 3 poles (-26.7885, 19.494) (-26.7885, 20.0991) (-26.3553, 20.3054) (-25.3996, 20.1678) knots 0 0 0 0 1 1 1 1
  spline S119 degree 3 poles (-25.3996, 20.1678) (-24.1825, 19.9891) (-23.4674, 19.3565) (-23.653, 18.607) knots 0 0 0 0 1 1 1 1
  spline S120 degree 3 poles (-23.653, 18.607) (-23.7149, 18.3663) (-23.935, 18.16) (-24.1412, 18.16) knots 0 0 0 0 1 1 1 1
  line L96 (-24.1412, 18.16) -> (-24.3131, 18.16)
  line L97 (-24.3131, 18.16) -> (-24.3131, 17.4312)
  line L98 (-24.3131, 17.4312) -> (-24.3131, 16.7023)
  line L99 (-24.3131, 16.7023) -> (-23.9006, 16.7298)
  spline S121 degree 3 poles (-23.9006, 16.7298) (-23.4468, 16.7642) (-23.2749, 16.8742) (-23.0755, 17.2661) knots 0 0 0 0 1 1 1 1
  spline S122 degree 3 poles (-23.0755, 17.2661) (-22.7935, 17.8162) (-22.7179, 18.8889) (-22.9104, 19.604) knots 0 0 0 0 1 1 1 1
  spline S123 degree 3 poles (-23.0204, 16.0628) (-23.1648, 16.111) (-27.4211, 16.9911) (-27.5243, 16.9911) knots 0 0 0 0 1 1 1 1
  spline S124 degree 3 poles (-27.5243, 16.9911) (-27.593, 16.9911) (-27.6137, 16.8467) (-27.6137, 16.4066) knots 0 0 0 0 1 1 1 1
  spline S125 degree 3 poles (-27.6137, 16.4066) (-27.6137, 16.0835) (-27.6068, 15.8222) (-27.593, 15.8222) knots 0 0 0 0 1 1 1 1
  spline S126 degree 3 poles (-27.593, 15.8222) (-27.4968, 15.8222) (-24.1481, 15.1277) (-24.1206, 15.1071) knots 0 0 0 0 1 1 1 1
  spline S127 degree 3 poles (-24.1206, 15.1071) (-24.1069, 15.0864) (-24.1825, 15.052) (-24.2856, 15.0245) knots 0 0 0 0 1 1 1 1
  spline S128 degree 3 poles (-24.2856, 15.0245) (-24.3957, 14.997) (-25.1795, 14.7976) (-26.0322, 14.5845) knots 0 0 0 0 1 1 1 1
  line L100 (-26.0322, 14.5845) -> (-27.5793, 14.1994)
  line L101 (-27.5793, 14.1994) -> (-27.5999, 13.2711)
  line L102 (-27.5999, 13.2711) -> (-27.6137, 12.3497)
  line L103 (-27.6137, 12.3497) -> (-25.3996, 11.8753)
  spline S129 degree 3 poles (-25.3996, 11.8753) (-24.1756, 11.614) (-23.1236, 11.3802) (-23.0548, 11.3665) knots 0 0 0 0 1 1 1 1
  spline S130 degree 3 poles (-23.0548, 11.3665) (-22.9448, 11.339) (-22.9311, 11.3871) (-22.9517, 11.9441) knots 0 0 0 0 1 1 1 1
  line L104 (-22.9517, 11.9441) -> (-22.9723, 12.5492)
  line L105 (-22.9723, 12.5492) -> (-24.6432, 12.9273)
  spline S131 degree 3 poles (-24.6432, 12.9273) (-25.764, 13.1818) (-26.2797, 13.3262) (-26.1903, 13.3605) knots 0 0 0 0 1 1 1 1
  spline S132 degree 3 poles (-26.1903, 13.3605) (-26.1216, 13.3949) (-25.4752, 13.5531) (-24.7601, 13.725) knots 0 0 0 0 1 1 1 1
  spline S133 degree 3 poles (-24.7601, 13.725) (-24.0381, 13.8969) (-23.3367, 14.0688) (-23.1923, 14.11) knots 0 0 0 0 1 1 1 1
  line L106 (-23.1923, 14.11) -> (-22.9379, 14.1788)
  line L107 (-22.9379, 14.1788) -> (-22.9379, 15.1071)
  spline S134 degree 3 poles (-22.9379, 15.1071) (-22.9379, 15.7878) (-22.9586, 16.0422) (-23.0204, 16.0628) knots 0 0 0 0 1 1 1 1
  spline S135 degree 3 poles (-25.1864, 11.1808) (-26.431, 11.4352) (-27.483, 11.6621) (-27.5243, 11.6828) knots 0 0 0 0 1 1 1 1
  spline S136 degree 3 poles (-27.5243, 11.6828) (-27.593, 11.7034) (-27.6137, 11.5521) (-27.6137, 11.0502) knots 0 0 0 0 1 1 1 1
  line L108 (-27.6137, 11.0502) -> (-27.6137, 10.3969)
  line L109 (-27.6137, 10.3969) -> (-27.3524, 10.3282)
  spline S137 degree 3 poles (-27.3524, 10.3282) (-27.2148, 10.2938) (-26.8435, 10.2113) (-26.5341, 10.1494) knots 0 0 0 0 1 1 1 1
  line L110 (-26.5341, 10.1494) -> (-25.9772, 10.0325)
  line L111 (-25.9772, 10.0325) -> (-25.9497, 9.1249)
  spline S138 degree 3 poles (-25.9497, 9.1249) (-25.9221, 8.1416) (-25.8053, 7.7428) (-25.4271, 7.344) knots 0 0 0 0 1 1 1 1
  spline S139 degree 3 poles (-25.4271, 7.344) (-24.8426, 6.7251) (-23.6049, 6.6357) (-23.2405, 7.1927) knots 0 0 0 0 1 1 1 1
  spline S140 degree 3 poles (-23.2405, 7.1927) (-23.0204, 7.5365) (-22.9379, 8.1072) (-22.9379, 9.4343) knots 0 0 0 0 1 1 1 1
  line L112 (-22.9379, 9.4343) -> (-22.9379, 10.7132)
  line L113 (-22.9379, 10.7132) -> (-25.1864, 11.1808)
  spline S141 degree 3 poles (-24.0381, 8.396) (-24.2513, 8.1828) (-24.5607, 8.2172) (-24.8357, 8.4923) knots 0 0 0 0 1 1 1 1
  spline S142 degree 3 poles (-24.8357, 8.4923) (-25.0626, 8.7192) (-25.0695, 8.7398) (-25.0695, 9.2761) knots 0 0 0 0 1 1 1 1
  line L114 (-25.0695, 9.2761) -> (-25.0695, 9.8262)
  line L115 (-25.0695, 9.8262) -> (-24.6363, 9.73)
  spline S143 degree 3 poles (-24.6363, 9.73) (-24.4025, 9.675) (-24.1412, 9.6199) (-24.0519, 9.5993) knots 0 0 0 0 1 1 1 1
  spline S144 degree 3 poles (-24.0519, 9.5993) (-23.9143, 9.5649) (-23.9006, 9.5237) (-23.9006, 9.0492) knots 0 0 0 0 1 1 1 1
  spline S145 degree 3 poles (-23.9006, 9.0492) (-23.9006, 8.6229) (-23.9281, 8.506) (-24.0381, 8.396) knots 0 0 0 0 1 1 1 1
  spline S146 degree 3 poles (-23.4124, 26.5213) (-23.7493, 27.0783) (-24.6707, 27.0508) (-24.9732, 26.4732) knots 0 0 0 0 1 1 1 1
  spline S147 degree 3 poles (-24.9732, 26.4732) (-25.2277, 25.9781) (-24.987, 25.3593) (-24.4644, 25.1736) knots 0 0 0 0 1 1 1 1
  spline S148 degree 3 poles (-24.4644, 25.1736) (-24.21, 25.0842) (-24.1412, 25.0842) (-23.8868, 25.1736) knots 0 0 0 0 1 1 1 1
  spline S149 degree 3 poles (-23.8868, 25.1736) (-23.3436, 25.3662) (-23.1098, 26.0263) (-23.4124, 26.5213) knots 0 0 0 0 1 1 1 1
  spline S150 degree 3 poles (-24.3613, 5.9) (-24.4919, 6.2713) (-24.9595, 6.6907) (-25.4752, 6.897) knots 0 0 0 0 1 1 1 1
  spline S151 degree 3 poles (-25.4752, 6.897) (-25.764, 7.007) (-26.0047, 7.0483) (-26.4516, 7.0552) knots 0 0 0 0 1 1 1 1
  spline S152 degree 3 poles (-26.4516, 7.0552) (-26.9742, 7.0552) (-27.0705, 7.0345) (-27.318, 6.8695) knots 0 0 0 0 1 1 1 1
  spline S153 degree 3 poles (-27.318, 6.8695) (-27.538, 6.7251) (-27.6137, 6.622) (-27.6755, 6.3676) knots 0 0 0 0 1 1 1 1
  spline S154 degree 3 poles (-27.6755, 6.3676) (-27.7924, 5.9069) (-27.7099, 5.4874) (-27.4349, 5.123) knots 0 0 0 0 1 1 1 1
  spline S155 degree 3 poles (-27.4349, 5.123) (-27.2148, 4.8411) (-27.208, 4.8204) (-27.3524, 4.8548) knots 0 0 0 0 1 1 1 1
  spline S156 degree 3 poles (-27.3524, 4.8548) (-27.5724, 4.903) (-28.8582, 5.1643) (-28.8926, 5.1643) knots 0 0 0 0 1 1 1 1
  spline S157 degree 3 poles (-28.8926, 5.1643) (-28.9132, 5.1643) (-28.9132, 4.8961) (-28.9064, 4.566) knots 0 0 0 0 1 1 1 1
  line L116 (-28.9064, 4.566) -> (-28.8857, 3.9678)
  line L117 (-28.8857, 3.9678) -> (-26.7542, 3.5002)
  spline S158 degree 3 poles (-26.7542, 3.5002) (-25.5783, 3.2458) (-24.5676, 3.0395) (-24.4988, 3.0327) knots 0 0 0 0 1 1 1 1
  spline S159 degree 3 poles (-24.4988, 3.0327) (-24.3957, 3.0327) (-24.3819, 3.1083) (-24.3819, 3.6171) knots 0 0 0 0 1 1 1 1
  line L118 (-24.3819, 3.6171) -> (-24.3819, 4.2016)
  line L119 (-24.3819, 4.2016) -> (-24.6019, 4.2497)
  line L120 (-24.6019, 4.2497) -> (-24.8151, 4.291)
  line L121 (-24.8151, 4.291) -> (-24.6501, 4.4354)
  spline S160 degree 3 poles (-24.6501, 4.4354) (-24.2306, 4.7998) (-24.1344, 5.2743) (-24.3613, 5.9) knots 0 0 0 0 1 1 1 1
  spline S161 degree 3 poles (-25.1314, 4.6554) (-25.3446, 4.4629) (-25.7021, 4.4491) (-26.1972, 4.6142) knots 0 0 0 0 1 1 1 1
  spline S162 degree 3 poles (-26.1972, 4.6142) (-26.6991, 4.7792) (-26.9948, 5.0542) (-26.9948, 5.3568) knots 0 0 0 0 1 1 1 1
  spline S163 degree 3 poles (-26.9948, 5.3568) (-26.9948, 5.5837) (-26.9398, 5.6662) (-26.7335, 5.7762) knots 0 0 0 0 1 1 1 1
  spline S164 degree 3 poles (-26.7335, 5.7762) (-26.4035, 5.9481) (-25.3239, 5.6593) (-25.1039, 5.343) knots 0 0 0 0 1 1 1 1
  spline S165 degree 3 poles (-25.1039, 5.343) (-24.9595, 5.1436) (-24.9732, 4.7929) (-25.1314, 4.6554) knots 0 0 0 0 1 1 1 1
  spline S166 degree 3 poles (-41.6, 30.9748) (-41.7468, 31.8085) (-42.3342, 32.6232) (-43.0731, 33.0305) knots 0 0 0 0 1 1 1 1
  spline S167 degree 3 poles (-43.0731, 33.0305) (-43.6036, 33.3242) (-43.8167, 33.3716) (-44.5557, 33.3716) knots 0 0 0 0 1 1 1 1
  spline S168 degree 3 poles (-44.5557, 33.3716) (-45.1525, 33.3716) (-45.2519, 33.3574) (-45.5646, 33.2437) knots 0 0 0 0 1 1 1 1
  spline S169 degree 3 poles (-45.5646, 33.2437) (-46.0572, 33.0637) (-46.5877, 32.7511) (-46.9098, 32.4479) knots 0 0 0 0 1 1 1 1
  line L122 (-46.9098, 32.4479) -> (-47.1845, 32.1827)
  line L123 (-47.1845, 32.1827) -> (-47.1845, 31.169)
  line L124 (-47.1845, 31.169) -> (-47.1845, 30.1507)
  line L125 (-47.1845, 30.1507) -> (-47.4118, 30.0086)
  spline S170 degree 3 poles (-47.4118, 30.0086) (-47.6913, 29.8286) (-47.7624, 29.6581) (-47.6297, 29.4828) knots 0 0 0 0 1 1 1 1
  spline S171 degree 3 poles (-47.6297, 29.4828) (-47.5303, 29.3502) (-47.5255, 29.3502) (-46.4124, 28.9712) knots 0 0 0 0 1 1 1 1
  spline S172 degree 3 poles (-46.4124, 28.9712) (-46.0051, 28.8339) (-45.6546, 28.706) (-45.6403, 28.6918) knots 0 0 0 0 1 1 1 1
  spline S173 degree 3 poles (-45.6403, 28.6918) (-45.6072, 28.6586) (-45.5835, 28.6634) (-46.6398, 28.4692) knots 0 0 0 0 1 1 1 1
  spline S174 degree 3 poles (-46.6398, 28.4692) (-48.1413, 28.1944) (-48.7571, 28.0571) (-48.8281, 27.9813) knots 0 0 0 0 1 1 1 1
  spline S175 degree 3 poles (-48.8281, 27.9813) (-48.9086, 27.9008) (-48.9228, 27.6308) (-48.8518, 27.5597) knots 0 0 0 0 1 1 1 1
  spline S176 degree 3 poles (-48.8518, 27.5597) (-48.8281, 27.536) (-48.3308, 27.3561) (-47.7481, 27.1619) knots 0 0 0 0 1 1 1 1
  spline S177 degree 3 poles (-47.7481, 27.1619) (-47.1655, 26.9676) (-46.6824, 26.7971) (-46.6729, 26.7877) knots 0 0 0 0 1 1 1 1
  spline S178 degree 3 poles (-46.6729, 26.7877) (-46.6635, 26.7782) (-46.7392, 26.7261) (-46.8387, 26.674) knots 0 0 0 0 1 1 1 1
  spline S179 degree 3 poles (-46.8387, 26.674) (-47.1561, 26.5129) (-47.1561, 26.5129) (-47.1845, 25.4993) knots 0 0 0 0 1 1 1 1
  line L126 (-47.1845, 25.4993) -> (-47.2082, 24.5804)
  line L127 (-47.2082, 24.5804) -> (-47.6818, 24.9783)
  spline S180 degree 3 poles (-47.6818, 24.9783) (-48.9465, 26.0487) (-50.5001, 27.6355) (-50.5807, 27.9387) knots 0 0 0 0 1 1 1 1
  spline S181 degree 3 poles (-50.5807, 27.9387) (-50.5949, 28.005) (-50.5712, 28.1187) (-50.5191, 28.2181) knots 0 0 0 0 1 1 1 1
  spline S182 degree 3 poles (-50.5191, 28.2181) (-50.3154, 28.6018) (-48.6813, 30.2549) (-47.8334, 30.9322) knots 0 0 0 0 1 1 1 1
  line L128 (-47.8334, 30.9322) -> (-47.5682, 31.1454)
  line L129 (-47.5682, 31.1454) -> (-47.5634, 31.5669)
  line L130 (-47.5634, 31.5669) -> (-47.5634, 31.9838)
  line L131 (-47.5634, 31.9838) -> (-47.7908, 31.8038)
  spline S183 degree 3 poles (-47.7908, 31.8038) (-48.3071, 31.3869) (-49.387, 30.3733) (-50.0786, 29.6675) knots 0 0 0 0 1 1 1 1
  spline S184 degree 3 poles (-50.0786, 29.6675) (-51.3385, 28.3697) (-51.4759, 28.0381) (-51.0022, 27.3939) knots 0 0 0 0 1 1 1 1
  spline S185 degree 3 poles (-51.0022, 27.3939) (-50.5143, 26.7261) (-48.6386, 24.9214) (-47.3976, 23.922) knots 0 0 0 0 1 1 1 1
  spline S186 degree 3 poles (-47.3976, 23.922) (-46.0572, 22.842) (-45.5219, 22.5957) (-44.5035, 22.5957) knots 0 0 0 0 1 1 1 1
  spline S187 degree 3 poles (-44.5035, 22.5957) (-44.0583, 22.5957) (-43.9352, 22.6147) (-43.5941, 22.7331) knots 0 0 0 0 1 1 1 1
  spline S188 degree 3 poles (-43.5941, 22.7331) (-42.5521, 23.0978) (-41.8463, 23.903) (-41.6237, 24.9783) knots 0 0 0 0 1 1 1 1
  spline S189 degree 3 poles (-41.6237, 24.9783) (-41.4295, 25.9066) (-41.6521, 26.7545) (-42.3152, 27.6213) knots 0 0 0 0 1 1 1 1
  line L132 (-42.3152, 27.6213) -> (-42.6278, 28.0334)
  line L133 (-42.6278, 28.0334) -> (-42.4857, 28.166)
  spline S190 degree 3 poles (-42.4857, 28.166) (-42.32, 28.3271) (-41.9837, 28.8291) (-41.8416, 29.1323) knots 0 0 0 0 1 1 1 1
  spline S191 degree 3 poles (-41.8416, 29.1323) (-41.6095, 29.6249) (-41.5005, 30.4396) (-41.6, 30.9748) knots 0 0 0 0 1 1 1 1
  spline S192 degree 3 poles (-42.3152, 24.8267) (-42.4431, 24.4478) (-42.6136, 24.1825) (-42.9262, 23.8746) knots 0 0 0 0 1 1 1 1
  spline S193 degree 3 poles (-42.9262, 23.8746) (-43.4236, 23.382) (-43.9873, 23.1783) (-44.7214, 23.2257) knots 0 0 0 0 1 1 1 1
  spline S194 degree 3 poles (-44.7214, 23.2257) (-45.1998, 23.2541) (-45.5693, 23.3773) (-46.0003, 23.6615) knots 0 0 0 0 1 1 1 1
  spline S195 degree 3 poles (-46.0003, 23.6615) (-46.545, 24.0215) (-46.5119, 23.9315) (-46.5308, 25.144) knots 0 0 0 0 1 1 1 1
  line L134 (-46.5308, 25.144) -> (-46.545, 26.1956)
  line L135 (-46.545, 26.1956) -> (-46.223, 26.3661)
  spline S196 degree 3 poles (-46.223, 26.3661) (-46.0477, 26.4561) (-45.8724, 26.584) (-45.8298, 26.6456) knots 0 0 0 0 1 1 1 1
  spline S197 degree 3 poles (-45.8298, 26.6456) (-45.7351, 26.7924) (-45.7777, 27.015) (-45.9245, 27.1097) knots 0 0 0 0 1 1 1 1
  spline S198 degree 3 poles (-45.9245, 27.1097) (-45.9814, 27.1476) (-46.384, 27.2945) (-46.8198, 27.4318) knots 0 0 0 0 1 1 1 1
  spline S199 degree 3 poles (-46.8198, 27.4318) (-47.5587, 27.6639) (-47.7529, 27.7587) (-47.5066, 27.7587) knots 0 0 0 0 1 1 1 1
  spline S200 degree 3 poles (-47.5066, 27.7587) (-47.4071, 27.7587) (-47.0945, 27.8155) (-46.0951, 28.0192) knots 0 0 0 0 1 1 1 1
  spline S201 degree 3 poles (-46.0951, 28.0192) (-44.7546, 28.2892) (-44.5509, 28.3413) (-44.4704, 28.4123) knots 0 0 0 0 1 1 1 1
  spline S202 degree 3 poles (-44.4704, 28.4123) (-44.3472, 28.5213) (-44.3662, 28.7818) (-44.4988, 28.8718) knots 0 0 0 0 1 1 1 1
  spline S203 degree 3 poles (-44.4988, 28.8718) (-44.5888, 28.9286) (-46.815, 29.7007) (-46.9003, 29.7007) knots 0 0 0 0 1 1 1 1
  spline S204 degree 3 poles (-46.9003, 29.7007) (-46.9098, 29.7007) (-46.8435, 29.7528) (-46.7535, 29.8144) knots 0 0 0 0 1 1 1 1
  spline S205 degree 3 poles (-46.7535, 29.8144) (-46.5403, 29.9612) (-46.5214, 30.0749) (-46.5214, 31.169) knots 0 0 0 0 1 1 1 1
  line L136 (-46.5214, 31.169) -> (-46.5214, 31.9648)
  line L137 (-46.5214, 31.9648) -> (-46.223, 32.1874)
  spline S206 degree 3 poles (-46.223, 32.1874) (-45.6688, 32.5995) (-45.1572, 32.7795) (-44.5414, 32.7795) knots 0 0 0 0 1 1 1 1
  spline S207 degree 3 poles (-44.5414, 32.7795) (-43.6367, 32.7795) (-42.8078, 32.249) (-42.4147, 31.4248) knots 0 0 0 0 1 1 1 1
  spline S208 degree 3 poles (-42.4147, 31.4248) (-42.2489, 31.0791) (-42.2347, 31.0127) (-42.2205, 30.5485) knots 0 0 0 0 1 1 1 1
  spline S209 degree 3 poles (-42.2205, 30.5485) (-42.1921, 29.767) (-42.3436, 29.3454) (-42.9026, 28.6492) knots 0 0 0 0 1 1 1 1
  spline S210 degree 3 poles (-42.9026, 28.6492) (-43.0778, 28.436) (-43.2341, 28.2086) (-43.2531, 28.1423) knots 0 0 0 0 1 1 1 1
  spline S211 degree 3 poles (-43.2531, 28.1423) (-43.3052, 27.9434) (-43.2247, 27.7539) (-42.9405, 27.4271) knots 0 0 0 0 1 1 1 1
  spline S212 degree 3 poles (-42.9405, 27.4271) (-42.6563, 27.0955) (-42.4005, 26.6645) (-42.3057, 26.3614) knots 0 0 0 0 1 1 1 1